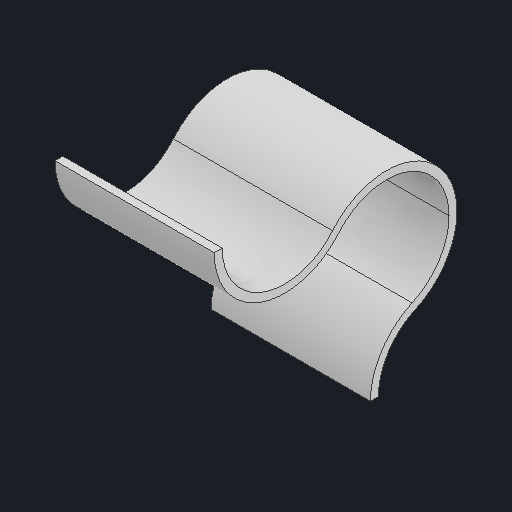
# Autodesk Inventor part: ribbon_1x10_100mm
Saved by Autodesk Inventor 2027.1 (Build 311270010, 270A)
## iProperties
Created: 2026-10-29
Part Number: ribbon_1x10_100mm
Material: Generic
Document SubType Name: Modeling
Designer: alexg
Density: 1 g/cm^3
Appearance: Default
Author: alexg
Autodesk Inventor part; units mm, degrees
ref_plane "XZ Plane" through (0, 0, 0) normal (0, 1, 0) x (-1, 0, 0)
ref_plane "XY Plane" through (0, 0, 0) normal (0, 0, 1) x (1, 0, 0)
ref_plane "Work Plane1" through (10.17, 0, 0) normal (1, 0, 0) x (0, 1, 0)
sketch "Ribbon sketch" plane through (10.17, 0, 0) normal (1, 0, 0) x (0, 1, 0)
  arc A0 (-54.6345, -4.4165) -> (-63.23, 1.15) centre (-63.2291, -8.2682) ccw
  arc A1 (-54.6345, -4.4165) -> (-44.944, -10.692) centre (-44.9418, -0.0689) ccw
  arc A2 (-44.944, -10.692) -> (-38.1173, 8.0636) centre (-44.9439, -0.0719) ccw
  arc A3 (-32.062, 24.7) -> (-38.1173, 8.0636) centre (-32.0622, 15.2799) ccw
  arc A4 (-53.5395, -3.9255) -> (-63.23, 2.35) centre (-63.2294, -8.2687) ccw
  arc A5 (-53.5395, -3.9255) -> (-44.944, -9.492) centre (-44.9421, -0.0694) ccw
  arc A6 (-44.944, -9.492) -> (-38.8887, 7.1444) centre (-44.9438, -0.0719) ccw
  arc A7 (-32.062, 25.9) -> (-38.8887, 7.1444) centre (-32.0621, 15.2799) ccw
  line L0 (-63.23, 1.15) -> (-63.23, 2.35)
  line L1 (-32.062, 24.7) -> (-32.062, 25.9)
  constraints: 16 point on circle, 8 centre point, 4 end point
extrude "Ribbon" add sketch "Ribbon sketch" along normal blind 24
body "Solid1"
